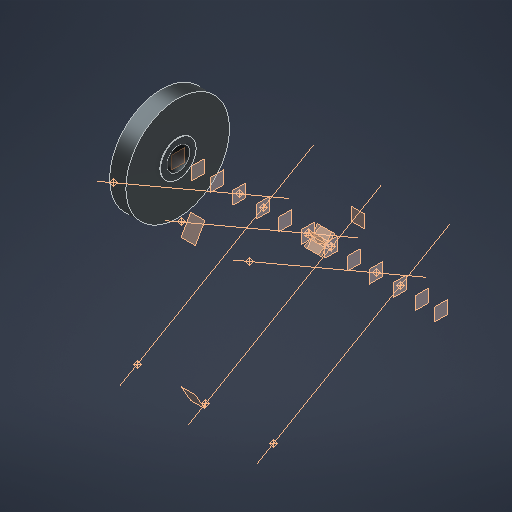
# Autodesk Inventor part: Crank_Pulley_SIMPLIFIED
Saved by Autodesk Inventor 2027.1 (Build 311270010, 270A)
## iProperties
Created: 2026-10-17
Part Number: Crank_Pulley_SIMPLIFIED
Material: Iron, Ductile
Document SubType Name: Modeling
Designer: kashyap
Density: 7.15 g/cm^3
Appearance: Iron Gray
Mass: 3432.11 g
Surface Area: 538.862 cm^2
Volume: 480.016 cm^3
Material_Status: Assumed for this reconstruction
Author: kashyap
Autodesk Inventor part; units mm, degrees
ref_plane "XZ Plane" through (0, 0, 0) normal (0, 1, 0) x (-1, 0, 0)
ref_plane "XY Plane" through (0, 0, 0) normal (0, 0, 1) x (1, 0, 0)
derived "V6_Engine_Master.ipt"
ref_plane "Bank_A_Plane" through (0, 0, 0) normal (0, 0.8660254, -0.5) x (-1, 0, 0)
ref_plane "Bank_B_Plane" through (0, 0, 0) normal (0, 0.8660254, 0.5) x (-1, 0, 0)
ref_plane "Bank_A_Perp_Plane" through (0, 0, 0) normal (0, 0.5, 0.8660254) x (-1, 0, 0)
ref_plane "Bank_B_Perp_Plane" through (0, 0, 0) normal (0, -0.5, 0.8660254) x (-1, 0, 0)
ref_plane "Bank_A_Deck_Plane" through (0, 112.9, 195.5485) normal (0, 0.5, 0.8660254) x (-1, 0, 0)
ref_plane "Bank_B_Deck_Plane" through (0, -112.9, 195.5485) normal (0, -0.5, 0.8660254) x (-1, 0, 0)
ref_plane "Cyl_A1_Station_Plane" through (-123.8, 0, 0) normal (1, 0, 0) x (0, 1, 0)
ref_plane "Cyl_A2_Station_Plane" through (-18.3, 0, 0) normal (1, 0, 0) x (0, 1, 0)
ref_plane "Cyl_A3_Station_Plane" through (87.2, 0, 0) normal (1, 0, 0) x (0, 1, 0)
ref_plane "Cyl_B1_Station_Plane" through (-87.2, 0, 0) normal (1, 0, 0) x (0, 1, 0)
ref_plane "Cyl_B2_Station_Plane" through (18.3, 0, 0) normal (1, 0, 0) x (0, 1, 0)
ref_plane "Cyl_B3_Station_Plane" through (123.8, 0, 0) normal (1, 0, 0) x (0, 1, 0)
ref_plane "Main_Bearing_Station_1" through (-158.25, 0, 0) normal (1, 0, 0) x (0, 1, 0)
ref_plane "Main_Bearing_Station_2" through (-52.75, 0, 0) normal (1, 0, 0) x (0, 1, 0)
ref_plane "Main_Bearing_Station_3" through (52.75, 0, 0) normal (1, 0, 0) x (0, 1, 0)
ref_plane "Main_Bearing_Station_4" through (158.25, 0, 0) normal (1, 0, 0) x (0, 1, 0)
ref_plane "Front_Interface" through (-188.25, 0, 0) normal (1, 0, 0) x (0, 1, 0)
ref_plane "Rear_Interface" through (188.25, 0, 0) normal (1, 0, 0) x (0, 1, 0)
ref_plane "Oil_Pan_Plane" through (0, 0, -60) normal (0, 0, 1) x (1, 0, 0)
ref_plane "Pulley_Hub_Inner_Plane" through (-218.25, 0, 0) normal (1, 0, 0) x (0, 1, 0)
sketch "SK_Hub" plane through (-218.25, 0, 0) normal (1, 0, 0) x (0, 1, 0)
  circle A0 centre (0, 0) radius 27.5
  circle A1 centre (0, 0) radius 17.5
  dimension "d20" = 55
  dimension "d21" = 35
  constraints: 2 centre point
  measures "d20" diameter of A0
  measures "d21" diameter of A1
extrude "Pulley_Hub" add sketch "SK_Hub" along normal blind -26
ref_plane "Pulley_Outer_Plane" through (-244.25, 0, 0) normal (1, 0, 0) x (0, 1, 0)
sketch "SK_Disc" plane through (-244.25, 0, 0) normal (1, 0, 0) x (0, 1, 0)
  circle A0 centre (0, 0) radius 80
  circle A1 centre (0, 0) radius 17.5
  dimension "d25" = 160
  dimension "d26" = 35
  constraints: 2 centre point
  measures "d25" diameter of A0
  measures "d26" diameter of A1
extrude "Pulley_Disc_SIMPLIFIED" add sketch "SK_Disc" along normal blind 25
equation "\"d21\" = Snout_Pulley_Dia"
equation "\"d22\" = -Snout_Sprocket_Length + Main_1_X - Crank_Pulley_Hub_Start - 0.5 * Main_Journal_Width - Snout_Pulley_Length"
equation "\"d25\" = Crank_Pulley_Dia"
equation "\"d26\" = Snout_Pulley_Dia"
equation "\"d27\" = Crank_Pulley_Width"
equation "\"Snout_Pulley_Dia\" = 35"
equation "\"Snout_Sprocket_Length\" = 30"
equation "\"Main_1_X\" = -158.25"
equation "\"Crank_Pulley_Hub_Start\" = -218.25"
equation "\"Main_Journal_Width\" = 22"
equation "\"Snout_Pulley_Length\" = 45"
equation "\"Crank_Pulley_Dia\" = 160"
equation "\"Crank_Pulley_Width\" = 25"
body "Solid1"
